Autodesk Fusion 360 part; units mm, degrees
(part 3 of 6)
sketch "A Seal Relief sketch" plane through (0.3536, 0.3536, 0) normal (0.707107, 0.707107, 0) x (0, 0, 1) in component "A Housing"
  circle A0 centre (0, 0) radius 9.75
  dimension "d695" = 19.5
  measures "d695" diameter of A0
extrude "A Seal Relief" cut sketch "A Seal Relief sketch" along normal blind 10.1 bodies 3 in component "A Housing"
ref_plane "WorkPlane21" through (0.3536, 0.3536, 12.125) normal (0.707107, 0.707107, 0) x (0, 0, 1) in component "A Housing"
sketch "A Front Bearing Seat sketch" plane through (0.3536, 0.3536, 0) normal (0.707107, 0.707107, 0) x (0, 0, 1) in component "A Housing"
  circle A0 centre (0, 0) radius 11.1
  dimension "d700" = 22.2
  measures "d700" diameter of A0
extrude "A Front Bearing Seat" cut sketch "A Front Bearing Seat sketch" along normal blind 7.1 bodies 3 in component "A Housing"
ref_plane "WorkPlane22" through (0.3536, 0.3536, 12.125) normal (0.707107, 0.707107, 0) x (0, 0, 1) in component "A Housing"
sketch "A Support Bolt seed" plane through (0.3536, 0.3536, 0) normal (0.707107, 0.707107, 0) x (0, 0, 1) in component "A Housing"
  line L0 (0, 0) -> (17, 0) construction
  circle A0 centre (17, 0) radius 1.65
  dimension "d705" = 17
  dimension "d706" = 3.3
  constraint horizontal L0
  measures "d705" distance of L0.start L0.end
  measures "d706" diameter of A0
extrude "A Support Bolt bore" cut sketch "A Support Bolt seed" along normal blind 10.1 bodies 3 in component "A Housing"
pattern_circular "A Support Bolt pattern" count 3 over 360 about axis through (0.3536, 0.3536, 0) along (0.707107, 0.707107, 0) of "A Support Bolt bore" in component "A Housing"
ref_plane "WorkPlane23" through (0.3536, 0.3536, 12.125) normal (0.707107, 0.707107, 0) x (0, 0, 1) in component "A Housing"
sketch "A Front Bearing Boss sketch" plane through (0.3536, 0.3536, 0) normal (0.707107, 0.707107, 0) x (0, 0, 1) in component "A Housing"
  circle A0 centre (0, 0) radius 22
  dimension "d713" = 44
  measures "d713" diameter of A0
chamfer "A Bearing Entry Chamfer" distance 0.4 angle 45 1 edges at (-2.4847, 3.1918, -10.3488) tangent chain off on bodies 3 in component "A Housing"
ref_plane "WorkPlane24" through (0, 0, 75) normal (0, 0, 1) x (1, 0, 0) in component "A Housing"
sketch "A Collar Driver Corridors" plane through (0, 0, 75) normal (0, 0, 1) x (1, 0, 0) in component "A Housing"
  circle A0 centre (6.7175, 15.9099) radius 3
  circle A1 centre (15.9099, 6.7175) radius 3
  dimension "d717" = 6.7175
  dimension "d718" = 15.9099
  dimension "d719" = 6
  dimension "d720" = 15.9099
  dimension "d721" = 6.7175
  dimension "d722" = 6
  measures "d717" horizontal distance of origin A0.centre
  measures "d718" vertical distance of origin A0.centre
  measures "d719" diameter of A0
  measures "d720" horizontal distance of origin A1.centre
  measures "d721" vertical distance of origin A1.centre
  measures "d722" diameter of A1
extrude "A Collar Service Channels" cut sketch "A Collar Driver Corridors" against normal blind 75 bodies 3 in component "A Housing"
ref_plane "WorkPlane17" through (-0.3536, -0.3536, 12.125) normal (0.707107, 0.707107, 0) x (0, 0, 1) in component "B Moving Body"
sketch "B Central Carrier sketch" plane through (-0.3536, -0.3536, 0) normal (0.707107, 0.707107, 0) x (0, 0, 1) in component "B Moving Body"
  circle A0 centre (0, 0) radius 38
  dimension "d727" = 76
  measures "d727" diameter of A0
extrude "B Central Carrier" add sketch "B Central Carrier sketch" against normal blind 22.5 separate body makes body 6 in component "B Moving Body"
ref_plane "WorkPlane18" through (-0.3536, -0.3536, 12.125) normal (0.707107, 0.707107, 0) x (0, 0, 1) in component "B Moving Body"
sketch "B Spoke 1 Profile" plane through (-0.3536, -0.3536, 0) normal (0.707107, 0.707107, 0) x (0, 0, 1) in component "B Moving Body"
  line L0 (-4.7984, -1.4054) -> (37.3643, -145.3579)
  line L1 (37.3643, -145.3579) -> (46.9611, -142.547)
  line L2 (46.9611, -142.547) -> (4.7984, 1.4054)
  line L3 (4.7984, 1.4054) -> (-4.7984, -1.4054)
  dimension "d732" = 4.7984
  dimension "d733" = 1.4054
  dimension "d734" = 37.3643
  dimension "d735" = 145.3579
  dimension "d736" = 46.9611
  dimension "d737" = 142.547
  dimension "d738" = 4.7984
  dimension "d739" = 1.4054
  measures "d732" horizontal distance of origin L0.start
  measures "d733" vertical distance of origin L0.start
  measures "d734" horizontal distance of origin L0.end
  measures "d735" vertical distance of origin L0.end
  measures "d736" horizontal distance of origin L1.end
  measures "d737" vertical distance of origin L1.end
  measures "d738" horizontal distance of origin L2.end
  measures "d739" vertical distance of origin L2.end
extrude "B Deep Spoke 1" add sketch "B Spoke 1 Profile" against normal blind 18 bodies 4 6 in component "B Moving Body"
sketch "B Spoke 2 Profile" plane through (-0.3536, -0.3536, 0) normal (0.707107, 0.707107, 0) x (0, 0, 1) in component "B Moving Body"
  line L0 (-2.5272, -4.3143) -> (126.9012, -80.1317)
  line L1 (126.9012, -80.1317) -> (131.9557, -71.5031)
  line L2 (131.9557, -71.5031) -> (2.5272, 4.3143)
  line L3 (2.5272, 4.3143) -> (-2.5272, -4.3143)
  dimension "d742" = 2.5272
  dimension "d743" = 4.3143
  dimension "d744" = 126.9012
  dimension "d745" = 80.1317
  dimension "d746" = 131.9557
  dimension "d747" = 71.5031
  dimension "d748" = 2.5272
  dimension "d749" = 4.3143
  measures "d742" horizontal distance of origin L0.start
  measures "d743" vertical distance of origin L0.start
  measures "d744" horizontal distance of origin L0.end
  measures "d745" vertical distance of origin L0.end
  measures "d746" horizontal distance of origin L1.end
  measures "d747" vertical distance of origin L1.end
  measures "d748" horizontal distance of origin L2.end
  measures "d749" vertical distance of origin L2.end
extrude "B Deep Spoke 2" add sketch "B Spoke 2 Profile" against normal blind 18 bodies 4 in component "B Moving Body"
sketch "B Spoke 3 Profile" plane through (-0.3536, -0.3536, 0) normal (0.707107, 0.707107, 0) x (0, 0, 1) in component "B Moving Body"
  line L0 (2.5272, -4.3143) -> (131.9557, 71.5031)
  line L1 (131.9557, 71.5031) -> (126.9012, 80.1317)
  line L2 (126.9012, 80.1317) -> (-2.5272, 4.3143)
  line L3 (-2.5272, 4.3143) -> (2.5272, -4.3143)
  dimension "d752" = 2.5272
  dimension "d753" = 4.3143
  dimension "d754" = 131.9557
  dimension "d755" = 71.5031
  dimension "d756" = 126.9012
  dimension "d757" = 80.1317
  dimension "d758" = 2.5272
  dimension "d759" = 4.3143
  measures "d752" horizontal distance of origin L0.start
  measures "d753" vertical distance of origin L0.start
  measures "d754" horizontal distance of origin L0.end
  measures "d755" vertical distance of origin L0.end
  measures "d756" horizontal distance of origin L1.end
  measures "d757" vertical distance of origin L1.end
  measures "d758" horizontal distance of origin L2.end
  measures "d759" vertical distance of origin L2.end
extrude "B Deep Spoke 3" add sketch "B Spoke 3 Profile" against normal blind 18 bodies 4 in component "B Moving Body"
sketch "B Spoke 4 Profile" plane through (-0.3536, -0.3536, 0) normal (0.707107, 0.707107, 0) x (0, 0, 1) in component "B Moving Body"
  line L0 (4.7984, -1.4054) -> (46.9611, 142.547)
  line L1 (46.9611, 142.547) -> (37.3643, 145.3579)
  line L2 (37.3643, 145.3579) -> (-4.7984, 1.4054)
  line L3 (-4.7984, 1.4054) -> (4.7984, -1.4054)
  dimension "d762" = 4.7984
  dimension "d763" = 1.4054
  dimension "d764" = 46.9611
  dimension "d765" = 142.547
  dimension "d766" = 37.3643
  dimension "d767" = 145.3579
  dimension "d768" = 4.7984
  dimension "d769" = 1.4054
  measures "d762" horizontal distance of origin L0.start
  measures "d763" vertical distance of origin L0.start
  measures "d764" horizontal distance of origin L0.end
  measures "d765" vertical distance of origin L0.end
  measures "d766" horizontal distance of origin L1.end
  measures "d767" vertical distance of origin L1.end
  measures "d768" horizontal distance of origin L2.end
  measures "d769" vertical distance of origin L2.end
extrude "B Deep Spoke 4" add sketch "B Spoke 4 Profile" against normal blind 18 bodies 4 in component "B Moving Body"
sketch "B Spoke 5 Profile" plane through (-0.3536, -0.3536, 0) normal (0.707107, 0.707107, 0) x (0, 0, 1) in component "B Moving Body"
  line L0 (4.7984, 1.4054) -> (-37.3643, 145.3579)
  line L1 (-37.3643, 145.3579) -> (-46.9611, 142.547)
  line L2 (-46.9611, 142.547) -> (-4.7984, -1.4054)
  line L3 (-4.7984, -1.4054) -> (4.7984, 1.4054)
  dimension "d772" = 4.7984
  dimension "d773" = 1.4054
  dimension "d774" = 37.3643
  dimension "d775" = 145.3579
  dimension "d776" = 46.9611
  dimension "d777" = 142.547
  dimension "d778" = 4.7984
  dimension "d779" = 1.4054
  measures "d772" horizontal distance of origin L0.start
  measures "d773" vertical distance of origin L0.start
  measures "d774" horizontal distance of origin L0.end
  measures "d775" vertical distance of origin L0.end
  measures "d776" horizontal distance of origin L1.end
  measures "d777" vertical distance of origin L1.end
  measures "d778" horizontal distance of origin L2.end
  measures "d779" vertical distance of origin L2.end
extrude "B Deep Spoke 5" add sketch "B Spoke 5 Profile" against normal blind 18 bodies 4 in component "B Moving Body"
sketch "B Spoke 6 Profile" plane through (-0.3536, -0.3536, 0) normal (0.707107, 0.707107, 0) x (0, 0, 1) in component "B Moving Body"
  line L0 (2.5272, 4.3143) -> (-126.9012, 80.1317)
  line L1 (-126.9012, 80.1317) -> (-131.9557, 71.5031)
  line L2 (-131.9557, 71.5031) -> (-2.5272, -4.3143)
  line L3 (-2.5272, -4.3143) -> (2.5272, 4.3143)
  dimension "d782" = 2.5272
  dimension "d783" = 4.3143
  dimension "d784" = 126.9012
  dimension "d785" = 80.1317
  dimension "d786" = 131.9557
  dimension "d787" = 71.5031
  dimension "d788" = 2.5272
  dimension "d789" = 4.3143
  measures "d782" horizontal distance of origin L0.start
  measures "d783" vertical distance of origin L0.start
  measures "d784" horizontal distance of origin L0.end
  measures "d785" vertical distance of origin L0.end
  measures "d786" horizontal distance of origin L1.end
  measures "d787" vertical distance of origin L1.end
  measures "d788" horizontal distance of origin L2.end
  measures "d789" vertical distance of origin L2.end
extrude "B Deep Spoke 6" add sketch "B Spoke 6 Profile" against normal blind 18 bodies 4 in component "B Moving Body"
sketch "B Spoke 7 Profile" plane through (-0.3536, -0.3536, 0) normal (0.707107, 0.707107, 0) x (0, 0, 1) in component "B Moving Body"
  line L0 (-2.5272, 4.3143) -> (-131.9557, -71.5031)
  line L1 (-131.9557, -71.5031) -> (-126.9012, -80.1317)
  line L2 (-126.9012, -80.1317) -> (2.5272, -4.3143)
  line L3 (2.5272, -4.3143) -> (-2.5272, 4.3143)
  dimension "d792" = 2.5272
  dimension "d793" = 4.3143
  dimension "d794" = 131.9557
  dimension "d795" = 71.5031
  dimension "d796" = 126.9012
  dimension "d797" = 80.1317
  dimension "d798" = 2.5272
  dimension "d799" = 4.3143
  measures "d792" horizontal distance of origin L0.start
  measures "d793" vertical distance of origin L0.start
  measures "d794" horizontal distance of origin L0.end
  measures "d795" vertical distance of origin L0.end
  measures "d796" horizontal distance of origin L1.end
  measures "d797" vertical distance of origin L1.end
  measures "d798" horizontal distance of origin L2.end
  measures "d799" vertical distance of origin L2.end
extrude "B Deep Spoke 7" add sketch "B Spoke 7 Profile" against normal blind 18 bodies 4 in component "B Moving Body"
sketch "B Spoke 8 Profile" plane through (-0.3536, -0.3536, 0) normal (0.707107, 0.707107, 0) x (0, 0, 1) in component "B Moving Body"
  line L0 (-4.7984, 1.4054) -> (-46.9611, -142.547)
  line L1 (-46.9611, -142.547) -> (-37.3643, -145.3579)
  line L2 (-37.3643, -145.3579) -> (4.7984, 1.4054)
  line L3 (4.7984, 1.4054) -> (-4.7984, 1.4054)
  dimension "d802" = 4.7984
  dimension "d803" = 1.4054
  dimension "d804" = 46.9611
  dimension "d805" = 142.547
  dimension "d806" = 37.3643
  dimension "d807" = 145.3579
  dimension "d808" = 4.7984
  dimension "d809" = 1.4054
  measures "d802" horizontal distance of origin L0.start
  measures "d803" vertical distance of origin L0.start
  measures "d804" horizontal distance of origin L0.end
  measures "d805" vertical distance of origin L0.end
  measures "d806" horizontal distance of origin L1.end
  measures "d807" vertical distance of origin L1.end
  measures "d808" horizontal distance of origin L2.end
  measures "d809" vertical distance of origin L2.end
extrude "B Deep Spoke 8" add sketch "B Spoke 8 Profile" against normal blind 18 bodies 4 in component "B Moving Body"
sketch "Spoke Outer Envelope (2)" plane through (0, 0, 0) normal (1, 0, 0) x (0, 0, -1) in component "B Moving Body"
  line L0 (75, 31.066) -> (31.066, 75)
  line L1 (31.066, 75) -> (-31.066, 75)
  line L2 (-31.066, 75) -> (-75, 31.066)
  line L3 (-75, 31.066) -> (-75, -31.066)
  line L4 (-75, -31.066) -> (-31.066, -75)
  line L5 (-31.066, -75) -> (31.066, -75)
  line L6 (31.066, -75) -> (75, -31.066)
  line L7 (75, -31.066) -> (75, 31.066)
  dimension "d812" = 150
  constraint horizontal L1
  measures "d812" vertical distance of L0.end L5.end
extrude "Clip Spokes to Octagon'" cut sketch "Spoke Outer Envelope (2)" along normal mid plane 260 keep common part bodies 4 in component "B Moving Body"
fillet "B Central Spoke Root Blends" radius 1 16 edges at (-31.2863, 17.8512, 15.3868) (3.6952, -17.1302, 35.0307) (-23.2315, 9.7965, 29.9762) (19.8388, -33.2738, -5.7899) (-23.2315, 9.7965, -29.9762) (-33.2076, 19.7726, -6.3678) (-31.2863, 17.8512, -15.3868) (-17.1302, 3.6952, -35.0307) (3.6952, -17.1302, -35.0307) (9.7965, -23.2315, -29.9762) (17.8512, -31.2863, -15.3868) (19.8388, -33.2738, 5.7899) (17.8512, -31.2863, 15.3868) (9.7965, -23.2315, 29.9762) (-17.1302, 3.6952, 35.0307) (-33.2738, 19.8388, 5.7899) on bodies 4 in component "B Moving Body"
ref_plane "WorkPlane19" through (-0.3536, -0.3536, 12.125) normal (0.707107, 0.707107, 0) x (0, 0, 1) in component "B Moving Body"
sketch "B Open Hub Cavity sketch" plane through (-0.3536, -0.3536, 0) normal (0.707107, 0.707107, 0) x (0, 0, 1) in component "B Moving Body"
  circle A0 centre (0, 0) radius 25.15
  dimension "d819" = 50.3
  measures "d819" diameter of A0
extrude "B Open Hub Cavity" cut sketch "B Open Hub Cavity sketch" against normal blind 22.5 bodies 4 in component "B Moving Body"
ref_plane "WorkPlane20" through (-0.3536, -0.3536, 12.125) normal (0.707107, 0.707107, 0) x (0, 0, 1) in component "B Moving Body"
sketch "B Four Mount Holes" plane through (-0.3536, -0.3536, 0) normal (0.707107, 0.707107, 0) x (0, 0, 1) in component "B Moving Body"
  circle A0 centre (22.6274, 22.6274) radius 2.15
  circle A1 centre (-22.6274, 22.6274) radius 2.15
  circle A2 centre (-22.6274, -22.6274) radius 2.15
  circle A3 centre (22.6274, -22.6274) radius 2.15
  dimension "d824" = 22.6274
  dimension "d825" = 22.6274
  dimension "d826" = 4.3
  dimension "d827" = 22.6274
  dimension "d828" = 22.6274
  dimension "d829" = 4.3
  dimension "d830" = 22.6274
  dimension "d831" = 22.6274
  dimension "d832" = 4.3
  dimension "d833" = 22.6274
  dimension "d834" = 22.6274
  dimension "d835" = 4.3
  measures "d824" horizontal distance of origin A0.centre
  measures "d825" vertical distance of origin A0.centre
  measures "d826" diameter of A0
  measures "d827" horizontal distance of origin A1.centre
  measures "d828" vertical distance of origin A1.centre
  measures "d829" diameter of A1
  measures "d830" horizontal distance of origin A2.centre
  measures "d831" vertical distance of origin A2.centre
  measures "d832" diameter of A2
  measures "d833" horizontal distance of origin A3.centre
  measures "d834" vertical distance of origin A3.centre
  measures "d835" diameter of A3
extrude "B M4 Through Holes" cut sketch "B Four Mount Holes" against normal blind 22.5 bodies 4 in component "B Moving Body"
sketch "B M4 Nut Pocket 1" plane through (-0.3536, -0.3536, 0) normal (0.707107, 0.707107, 0) x (0, 0, 1) in component "B Moving Body"
  circle A0 centre (22.6274, 22.6274) radius 4.1569 construction
  line L0 (26.7843, 22.6274) -> (24.7059, 26.2274)
  line L1 (24.7059, 26.2274) -> (20.549, 26.2274)
  line L2 (20.549, 26.2274) -> (18.4705, 22.6274)
  line L3 (18.4705, 22.6274) -> (20.549, 19.0274)
  line L4 (20.549, 19.0274) -> (24.7059, 19.0274)
  line L5 (24.7059, 19.0274) -> (26.7843, 22.6274)
  dimension "d838" = 22.6274
  dimension "d839" = 22.6274
  dimension "d840" = 8.3138
  constraint coincident A0 L0.start
  constraint coincident A0 L0.end
  constraint coincident A0 L1.end
  constraint coincident A0 L2.end
  constraint coincident A0 L3.end
  constraint coincident A0 L4.end
  constraint equal L0 L1
  constraint equal L0 L2
  constraint equal L0 L3
  constraint equal L0 L4
  constraint equal L0 L5
  constraint horizontal L1
  measures "d838" horizontal distance of origin A0.centre
  measures "d839" vertical distance of origin A0.centre
  measures "d840" diameter of A0
extrude "B Open M4 Nut Trap 1" cut sketch "B M4 Nut Pocket 1" against normal blind 4 bodies 4 in component "B Moving Body"
sketch "B M4 Nut Pocket 2" plane through (-0.3536, -0.3536, 0) normal (0.707107, 0.707107, 0) x (0, 0, 1) in component "B Moving Body"
  circle A0 centre (-22.6274, 22.6274) radius 4.1569 construction
  line L0 (-18.4705, 22.6274) -> (-20.549, 26.2274)
  line L1 (-20.549, 26.2274) -> (-24.7059, 26.2274)
  line L2 (-24.7059, 26.2274) -> (-26.7843, 22.6274)
  line L3 (-26.7843, 22.6274) -> (-24.7059, 19.0274)
  line L4 (-24.7059, 19.0274) -> (-20.549, 19.0274)
  line L5 (-20.549, 19.0274) -> (-18.4705, 22.6274)
  dimension "d843" = 22.6274
  dimension "d844" = 22.6274
  dimension "d845" = 8.3138
  constraint coincident A0 L0.start
  constraint coincident A0 L0.end
  constraint coincident A0 L1.end
  constraint coincident A0 L2.end
  constraint coincident A0 L3.end
  constraint coincident A0 L4.end
  constraint equal L0 L1
  constraint equal L0 L2
  constraint equal L0 L3
  constraint equal L0 L4
  constraint equal L0 L5
  constraint horizontal L1
  measures "d843" horizontal distance of origin A0.centre
  measures "d844" vertical distance of origin A0.centre
  measures "d845" diameter of A0
extrude "B Open M4 Nut Trap 2" cut sketch "B M4 Nut Pocket 2" against normal blind 4 bodies 4 in component "B Moving Body"
sketch "B M4 Nut Pocket 3" plane through (-0.3536, -0.3536, 0) normal (0.707107, 0.707107, 0) x (0, 0, 1) in component "B Moving Body"
  circle A0 centre (-22.6274, -22.6274) radius 4.1569 construction
  line L0 (-18.4705, -22.6274) -> (-20.549, -19.0274)
  line L1 (-20.549, -19.0274) -> (-24.7059, -19.0274)
  line L2 (-24.7059, -19.0274) -> (-26.7843, -22.6274)
  line L3 (-26.7843, -22.6274) -> (-24.7059, -26.2274)
  line L4 (-24.7059, -26.2274) -> (-20.549, -26.2274)
  line L5 (-20.549, -26.2274) -> (-18.4705, -22.6274)
  dimension "d848" = 22.6274
  dimension "d849" = 22.6274
  dimension "d850" = 8.3138
  constraint coincident A0 L0.start
  constraint coincident A0 L0.end
  constraint coincident A0 L1.end
  constraint coincident A0 L2.end
  constraint coincident A0 L3.end
  constraint coincident A0 L4.end
  constraint equal L0 L1
  constraint equal L0 L2
  constraint equal L0 L3
  constraint equal L0 L4
  constraint equal L0 L5
  constraint horizontal L1
  measures "d848" horizontal distance of origin A0.centre
  measures "d849" vertical distance of origin A0.centre
  measures "d850" diameter of A0
extrude "B Open M4 Nut Trap 3" cut sketch "B M4 Nut Pocket 3" against normal blind 4 bodies 4 in component "B Moving Body"
sketch "B M4 Nut Pocket 4" plane through (-0.3536, -0.3536, 0) normal (0.707107, 0.707107, 0) x (0, 0, 1) in component "B Moving Body"
  circle A0 centre (22.6274, -22.6274) radius 4.1569 construction
  line L0 (26.7843, -22.6274) -> (24.7059, -19.0274)
  line L1 (24.7059, -19.0274) -> (20.549, -19.0274)
  line L2 (20.549, -19.0274) -> (18.4705, -22.6274)
  line L3 (18.4705, -22.6274) -> (20.549, -26.2274)
  line L4 (20.549, -26.2274) -> (24.7059, -26.2274)
  line L5 (24.7059, -26.2274) -> (26.7843, -22.6274)
  dimension "d853" = 22.6274
  dimension "d854" = 22.6274
  dimension "d855" = 8.3138
  constraint coincident A0 L0.start
  constraint coincident A0 L0.end
  constraint coincident A0 L1.end
  constraint coincident A0 L2.end
  constraint coincident A0 L3.end
  constraint coincident A0 L4.end
  constraint equal L0 L1
  constraint equal L0 L2
  constraint equal L0 L3
  constraint equal L0 L4
  constraint equal L0 L5
  constraint horizontal L1
  measures "d853" horizontal distance of origin A0.centre
  measures "d854" vertical distance of origin A0.centre
  measures "d855" diameter of A0
extrude "B Open M4 Nut Trap 4" cut sketch "B M4 Nut Pocket 4" against normal blind 4 bodies 4 in component "B Moving Body"
sketch "B Hub Service Slots" plane through (0, 0, 0) normal (0, 0, 1) x (1, 0, 0) in component "B Moving Body"
  line L0 (-14.8492, 3.5355) -> (-30.4056, -12.0208)
  line L1 (-30.4056, -12.0208) -> (-12.0208, -30.4056)
  line L2 (-12.0208, -30.4056) -> (3.5355, -14.8492)
  line L3 (3.5355, -14.8492) -> (-14.8492, 3.5355)
  dimension "d858" = 14.8492
  dimension "d859" = 3.5355
  dimension "d860" = 30.4056
  dimension "d861" = 12.0208
  dimension "d862" = 12.0208
  dimension "d863" = 30.4056
  dimension "d864" = 3.5355
  dimension "d865" = 14.8492
  measures "d858" horizontal distance of origin L0.start
  measures "d859" vertical distance of origin L0.start
  measures "d860" horizontal distance of origin L0.end
  measures "d861" vertical distance of origin L0.end
  measures "d862" horizontal distance of origin L1.end
  measures "d863" vertical distance of origin L1.end
  measures "d864" horizontal distance of origin L2.end
  measures "d865" vertical distance of origin L2.end
extrude "B Hub Side Access" cut sketch "B Hub Service Slots" along normal mid plane 76 bodies 4 in component "B Moving Body"
component "A Housing" placed x (1, 0, 0) y (0, 1, 0) z (0, 0, 1) at (0, 0, 0)
component "B Moving Body" placed x (1, 0, 0) y (0, 1, 0) z (0, 0, 1) at (0, 0, 0)
equation "bodyWidth = 150 mm" comment "Regular octagon across flats; corner diameter is larger."
equation "bodyLength = 260 mm" comment "Overall straight length of the shared master blank."
equation "splitAngle = 45 deg" comment "Keep this lesson angle at45 degrees."
equation "faceGap = 1 mm" comment "Gap between the two printed joint faces."
equation "wall = 4.5 mm" comment "Integrated shell and side brace radial thickness."
equation "faceHalfWidth = bodyWidth * ( sqrt(2) - 1 ) / 2" comment "Half-width of each outer planar facet."
equation "memberWidth = 8 mm" comment "Nominal brace and corner chord width in a facet."
equation "nodeHalfWidth = faceHalfWidth - memberWidth / 2" comment "Chord centerlines measured from facet center."
equation "jointNodeQ = 7 mm" comment "First truss skeleton row from the center joint plane."
equation "endRim = 10 mm" comment "Uncut axial rim at each distant end."
equation "endNodeX = bodyLength / 2 - endRim + memberWidth / 2" comment "Last skeleton row before aperture inset."
equation "apertureRadius = 1.5 mm" comment "Rounded internal corners at triangular openings."
equation "spokeWidth = 10 mm" comment "Width of each deep bearing bulkhead spoke."
equation "spokeDepth = 18 mm" comment "Bulkhead depth normal to the diagonal joint face."
equation "carrierOD = 52 mm" comment "Outside of integrated A front bearing carrier."
equation "rearCarrierClearance = 46 mm" comment "Internal carrier relief above front bearing shoulder."
equation "tubeCornerChamfer = 0.5 mm" comment "Exposed outside octagon corner bevel."
equation "tubeRimChamfer = 0.3 mm" comment "End rim and print-contact edge relief."
equation "cordStation = bodyLength / 2 - endRim / 2" comment "Load-test cord port center measured along body X."
equation "bearingOD = 22 mm" comment "608 measured outside diameter."
equation "bearingID = 8 mm" comment "608 bore."
equation "bearingWidth = 7 mm" comment "608 width."
equation "seatAllowance = 0.2 mm" comment "Trial DIAMETRAL clearance; choose with printed coupon."
equation "seatDiameter = bearingOD + seatAllowance" comment "Measured fit controls this."
equation "coreOD = 44 mm" comment "Bearing holder outer diameter."
equation "raceRelief = 19.5 mm" comment "Outer-ring shoulder opening; verify seals."
equation "frontSeatDepth = 7.1 mm" comment "0.1 mm outer-ring axial allowance."
equation "rearSeatDepth = 7.2 mm" comment "0.2 mm outer-ring axial float."
equation "shoulder = 3 mm" comment "Backing behind each bearing seat."
equation "supportSpacer = 12 mm" comment "Purchased metal M3 spacer length."
equation "supportCircle = 34 mm" comment "Three M3 support bolts."
equation "supportSpacerOD = 6 mm" comment "Purchased spacer outside diameter."
equation "capThickness = 3 mm" comment "Both printed outer-ring retaining caps."
equation "m3Clearance = 3.3 mm" comment "M3 through holes."
equation "m4Clearance = 4.3 mm" comment "M4 through holes."
equation "qFront = faceGap / 2" comment "Front bearing starts at A mating face."
equation "qFrontBack = qFront + frontSeatDepth + shoulder" comment "End of integrated A holder."
equation "qRearBase = qFrontBack + supportSpacer" comment "Start of removable rear holder."
equation "qRearBearing = qRearBase + shoulder" comment "Rear bearing inner end."
equation "qRearEnd = qRearBearing + rearSeatDepth" comment "Rear holder outer end."
equation "bearingSpacing = qRearBearing - qFront" comment "Derived support-center spacing, not a bearing rating."
equation "mountOD = 76 mm" comment "B mount and F flange outside diameter."
equation "mountCircle = 64 mm" comment "Four M4 attachment holes."
equation "mountOpening = 50.3 mm" comment "B through opening."
equation "hubFace = -23 mm" comment "Metal hub flat mounting face."
equation "adapterThickness = 6 mm" comment "F flange and metal compression sleeve length."
equation "pilotDiameter = 50 mm" comment "F shallow centering pilot."
equation "pilotInside = 34 mm" comment "Clearance around metal hub."
equation "pilotHeight = 2 mm" comment "Short pilot only."
equation "hubHoleSpacing = 16 mm" comment "Metal Sonic hub square hole spacing."
equation "sleeveOD = 8 mm" comment "M4 metal compression sleeves."
equation "sleeveAllowance = 0.2 mm" comment "Trial DIAMETRAL sleeve clearance."
equation "shaftClearance = 8.5 mm" comment "F clearance hole; not a bearing."
equation "nutAF = 7.2 mm" comment "M4 nominal 7 AF nut trial pocket."
equation "nutDepth = 4 mm" comment "Open front M4 nut pocket."
equation "rootRadius = 1 mm" comment "Hub-to-wall blend."
equation "entryChamfer = 0.4 mm" comment "Assembly lead-in."
equation "bedRelief = 0.3 mm" comment "Bed-contact edge allowance."
equation "d59 = bodyWidth"
equation "d60 = bodyLength"
equation "d62 = splitAngle"
equation "d64 = -faceGap / 2"
equation "d65 = -faceGap / 2"
equation "d66 = wall"
equation "d67 = wall"
equation "d70 = bodyWidth / 2"
equation "d72 = abs(( 1 ) * ( ( ( 1 ) * jointNodeQ * sqrt(2) - bodyWidth / 2 * cos(0 deg) + ( ( -1 ) * nodeHalfWidth ) * sin(0 deg) ) + ( 0 ) * ( ( 1 ) * endNodeX - ( ( 1 ) * jointNodeQ * sqrt(2) - bodyWidth / 2 * cos(0 deg) + ( ( -1 ) * nodeHalfWidth ) * sin(0 deg) ) ) ) + ( 0 ) * ( ( -1 ) * nodeHalfWidth ))"
equation "d73 = abs(( 0 ) * ( ( ( 1 ) * jointNodeQ * sqrt(2) - bodyWidth / 2 * cos(0 deg) + ( ( -1 ) * nodeHalfWidth ) * sin(0 deg) ) + ( 0 ) * ( ( 1 ) * endNodeX - ( ( 1 ) * jointNodeQ * sqrt(2) - bodyWidth / 2 * cos(0 deg) + ( ( -1 ) * nodeHalfWidth ) * sin(0 deg) ) ) ) + ( -1 ) * ( ( -1 ) * nodeHalfWidth ))"
equation "d74 = abs(( 1 ) * ( ( ( 1 ) * jointNodeQ * sqrt(2) - bodyWidth / 2 * cos(0 deg) + ( ( 1 ) * nodeHalfWidth ) * sin(0 deg) ) + ( 0 ) * ( ( 1 ) * endNodeX - ( ( 1 ) * jointNodeQ * sqrt(2) - bodyWidth / 2 * cos(0 deg) + ( ( 1 ) * nodeHalfWidth ) * sin(0 deg) ) ) ) + ( 0 ) * ( ( 1 ) * nodeHalfWidth ))"
equation "d75 = abs(( 0 ) * ( ( ( 1 ) * jointNodeQ * sqrt(2) - bodyWidth / 2 * cos(0 deg) + ( ( 1 ) * nodeHalfWidth ) * sin(0 deg) ) + ( 0 ) * ( ( 1 ) * endNodeX - ( ( 1 ) * jointNodeQ * sqrt(2) - bodyWidth / 2 * cos(0 deg) + ( ( 1 ) * nodeHalfWidth ) * sin(0 deg) ) ) ) + ( -1 ) * ( ( 1 ) * nodeHalfWidth ))"
equation "d76 = abs(( 1 ) * ( ( ( 1 ) * jointNodeQ * sqrt(2) - bodyWidth / 2 * cos(0 deg) + ( ( -1 ) * nodeHalfWidth ) * sin(0 deg) ) + ( 0.666666666666667 ) * ( ( 1 ) * endNodeX - ( ( 1 ) * jointNodeQ * sqrt(2) - bodyWidth / 2 * cos(0 deg) + ( ( -1 ) * nodeHalfWidth ) * sin(0 deg) ) ) ) + ( 0 ) * ( ( -1 ) * nodeHalfWidth ))"
equation "d77 = abs(( 0 ) * ( ( ( 1 ) * jointNodeQ * sqrt(2) - bodyWidth / 2 * cos(0 deg) + ( ( -1 ) * nodeHalfWidth ) * sin(0 deg) ) + ( 0.666666666666667 ) * ( ( 1 ) * endNodeX - ( ( 1 ) * jointNodeQ * sqrt(2) - bodyWidth / 2 * cos(0 deg) + ( ( -1 ) * nodeHalfWidth ) * sin(0 deg) ) ) ) + ( -1 ) * ( ( -1 ) * nodeHalfWidth ))"
equation "d78 = -memberWidth / 2"
equation "d79 = -( wall + 0.2 mm )"
equation "d81 = abs(( 1 ) * ( ( ( 1 ) * jointNodeQ * sqrt(2) - bodyWidth / 2 * cos(0 deg) + ( ( 1 ) * nodeHalfWidth ) * sin(0 deg) ) + ( 0 ) * ( ( 1 ) * endNodeX - ( ( 1 ) * jointNodeQ * sqrt(2) - bodyWidth / 2 * cos(0 deg) + ( ( 1 ) * nodeHalfWidth ) * sin(0 deg) ) ) ) + ( 0 ) * ( ( 1 ) * nodeHalfWidth ))"
equation "d82 = abs(( 0 ) * ( ( ( 1 ) * jointNodeQ * sqrt(2) - bodyWidth / 2 * cos(0 deg) + ( ( 1 ) * nodeHalfWidth ) * sin(0 deg) ) + ( 0 ) * ( ( 1 ) * endNodeX - ( ( 1 ) * jointNodeQ * sqrt(2) - bodyWidth / 2 * cos(0 deg) + ( ( 1 ) * nodeHalfWidth ) * sin(0 deg) ) ) ) + ( -1 ) * ( ( 1 ) * nodeHalfWidth ))"
equation "d83 = abs(( 1 ) * ( ( ( 1 ) * jointNodeQ * sqrt(2) - bodyWidth / 2 * cos(0 deg) + ( ( -1 ) * nodeHalfWidth ) * sin(0 deg) ) + ( 0.666666666666667 ) * ( ( 1 ) * endNodeX - ( ( 1 ) * jointNodeQ * sqrt(2) - bodyWidth / 2 * cos(0 deg) + ( ( -1 ) * nodeHalfWidth ) * sin(0 deg) ) ) ) + ( 0 ) * ( ( -1 ) * nodeHalfWidth ))"
equation "d84 = abs(( 0 ) * ( ( ( 1 ) * jointNodeQ * sqrt(2) - bodyWidth / 2 * cos(0 deg) + ( ( -1 ) * nodeHalfWidth ) * sin(0 deg) ) + ( 0.666666666666667 ) * ( ( 1 ) * endNodeX - ( ( 1 ) * jointNodeQ * sqrt(2) - bodyWidth / 2 * cos(0 deg) + ( ( -1 ) * nodeHalfWidth ) * sin(0 deg) ) ) ) + ( -1 ) * ( ( -1 ) * nodeHalfWidth ))"
equation "d85 = abs(( 1 ) * ( ( ( 1 ) * jointNodeQ * sqrt(2) - bodyWidth / 2 * cos(0 deg) + ( ( 1 ) * nodeHalfWidth ) * sin(0 deg) ) + ( 0.833333333333333 ) * ( ( 1 ) * endNodeX - ( ( 1 ) * jointNodeQ * sqrt(2) - bodyWidth / 2 * cos(0 deg) + ( ( 1 ) * nodeHalfWidth ) * sin(0 deg) ) ) ) + ( 0 ) * ( ( 1 ) * nodeHalfWidth ))"
equation "d86 = abs(( 0 ) * ( ( ( 1 ) * jointNodeQ * sqrt(2) - bodyWidth / 2 * cos(0 deg) + ( ( 1 ) * nodeHalfWidth ) * sin(0 deg) ) + ( 0.833333333333333 ) * ( ( 1 ) * endNodeX - ( ( 1 ) * jointNodeQ * sqrt(2) - bodyWidth / 2 * cos(0 deg) + ( ( 1 ) * nodeHalfWidth ) * sin(0 deg) ) ) ) + ( -1 ) * ( ( 1 ) * nodeHalfWidth ))"
equation "d87 = memberWidth / 2"
equation "d88 = -( wall + 0.2 mm )"
equation "d90 = abs(( 1 ) * ( ( ( 1 ) * jointNodeQ * sqrt(2) - bodyWidth / 2 * cos(0 deg) + ( ( -1 ) * nodeHalfWidth ) * sin(0 deg) ) + ( 0.666666666666667 ) * ( ( 1 ) * endNodeX - ( ( 1 ) * jointNodeQ * sqrt(2) - bodyWidth / 2 * cos(0 deg) + ( ( -1 ) * nodeHalfWidth ) * sin(0 deg) ) ) ) + ( 0 ) * ( ( -1 ) * nodeHalfWidth ))"
equation "d91 = abs(( 0 ) * ( ( ( 1 ) * jointNodeQ * sqrt(2) - bodyWidth / 2 * cos(0 deg) + ( ( -1 ) * nodeHalfWidth ) * sin(0 deg) ) + ( 0.666666666666667 ) * ( ( 1 ) * endNodeX - ( ( 1 ) * jointNodeQ * sqrt(2) - bodyWidth / 2 * cos(0 deg) + ( ( -1 ) * nodeHalfWidth ) * sin(0 deg) ) ) ) + ( -1 ) * ( ( -1 ) * nodeHalfWidth ))"
equation "d92 = abs(( 1 ) * ( ( ( 1 ) * jointNodeQ * sqrt(2) - bodyWidth / 2 * cos(0 deg) + ( ( 1 ) * nodeHalfWidth ) * sin(0 deg) ) + ( 0.833333333333333 ) * ( ( 1 ) * endNodeX - ( ( 1 ) * jointNodeQ * sqrt(2) - bodyWidth / 2 * cos(0 deg) + ( ( 1 ) * nodeHalfWidth ) * sin(0 deg) ) ) ) + ( 0 ) * ( ( 1 ) * nodeHalfWidth ))"
equation "d93 = abs(( 0 ) * ( ( ( 1 ) * jointNodeQ * sqrt(2) - bodyWidth / 2 * cos(0 deg) + ( ( 1 ) * nodeHalfWidth ) * sin(0 deg) ) + ( 0.833333333333333 ) * ( ( 1 ) * endNodeX - ( ( 1 ) * jointNodeQ * sqrt(2) - bodyWidth / 2 * cos(0 deg) + ( ( 1 ) * nodeHalfWidth ) * sin(0 deg) ) ) ) + ( -1 ) * ( ( 1 ) * nodeHalfWidth ))"
equation "d94 = abs(( 1 ) * ( ( ( 1 ) * jointNodeQ * sqrt(2) - bodyWidth / 2 * cos(0 deg) + ( ( -1 ) * nodeHalfWidth ) * sin(0 deg) ) + ( 1 ) * ( ( 1 ) * endNodeX - ( ( 1 ) * jointNodeQ * sqrt(2) - bodyWidth / 2 * cos(0 deg) + ( ( -1 ) * nodeHalfWidth ) * sin(0 deg) ) ) ) + ( 0 ) * ( ( -1 ) * nodeHalfWidth ))"
equation "d95 = abs(( 0 ) * ( ( ( 1 ) * jointNodeQ * sqrt(2) - bodyWidth / 2 * cos(0 deg) + ( ( -1 ) * nodeHalfWidth ) * sin(0 deg) ) + ( 1 ) * ( ( 1 ) * endNodeX - ( ( 1 ) * jointNodeQ * sqrt(2) - bodyWidth / 2 * cos(0 deg) + ( ( -1 ) * nodeHalfWidth ) * sin(0 deg) ) ) ) + ( -1 ) * ( ( -1 ) * nodeHalfWidth ))"
equation "d96 = -memberWidth / 2"
equation "d97 = -( wall + 0.2 mm )"
equation "d99 = abs(( 1 ) * ( ( ( 1 ) * jointNodeQ * sqrt(2) - bodyWidth / 2 * cos(0 deg) + ( ( 1 ) * nodeHalfWidth ) * sin(0 deg) ) + ( 0.833333333333333 ) * ( ( 1 ) * endNodeX - ( ( 1 ) * jointNodeQ * sqrt(2) - bodyWidth / 2 * cos(0 deg) + ( ( 1 ) * nodeHalfWidth ) * sin(0 deg) ) ) ) + ( 0 ) * ( ( 1 ) * nodeHalfWidth ))"
equation "d100 = abs(( 0 ) * ( ( ( 1 ) * jointNodeQ * sqrt(2) - bodyWidth / 2 * cos(0 deg) + ( ( 1 ) * nodeHalfWidth ) * sin(0 deg) ) + ( 0.833333333333333 ) * ( ( 1 ) * endNodeX - ( ( 1 ) * jointNodeQ * sqrt(2) - bodyWidth / 2 * cos(0 deg) + ( ( 1 ) * nodeHalfWidth ) * sin(0 deg) ) ) ) + ( -1 ) * ( ( 1 ) * nodeHalfWidth ))"
equation "d101 = abs(( 1 ) * ( ( ( 1 ) * jointNodeQ * sqrt(2) - bodyWidth / 2 * cos(0 deg) + ( ( -1 ) * nodeHalfWidth ) * sin(0 deg) ) + ( 1 ) * ( ( 1 ) * endNodeX - ( ( 1 ) * jointNodeQ * sqrt(2) - bodyWidth / 2 * cos(0 deg) + ( ( -1 ) * nodeHalfWidth ) * sin(0 deg) ) ) ) + ( 0 ) * ( ( -1 ) * nodeHalfWidth ))"
equation "d102 = abs(( 0 ) * ( ( ( 1 ) * jointNodeQ * sqrt(2) - bodyWidth / 2 * cos(0 deg) + ( ( -1 ) * nodeHalfWidth ) * sin(0 deg) ) + ( 1 ) * ( ( 1 ) * endNodeX - ( ( 1 ) * jointNodeQ * sqrt(2) - bodyWidth / 2 * cos(0 deg) + ( ( -1 ) * nodeHalfWidth ) * sin(0 deg) ) ) ) + ( -1 ) * ( ( -1 ) * nodeHalfWidth ))"
equation "d103 = abs(( 1 ) * ( ( ( 1 ) * jointNodeQ * sqrt(2) - bodyWidth / 2 * cos(0 deg) + ( ( 1 ) * nodeHalfWidth ) * sin(0 deg) ) + ( 1 ) * ( ( 1 ) * endNodeX - ( ( 1 ) * jointNodeQ * sqrt(2) - bodyWidth / 2 * cos(0 deg) + ( ( 1 ) * nodeHalfWidth ) * sin(0 deg) ) ) ) + ( 0 ) * ( ( 1 ) * nodeHalfWidth ))"
equation "d104 = abs(( 0 ) * ( ( ( 1 ) * jointNodeQ * sqrt(2) - bodyWidth / 2 * cos(0 deg) + ( ( 1 ) * nodeHalfWidth ) * sin(0 deg) ) + ( 1 ) * ( ( 1 ) * endNodeX - ( ( 1 ) * jointNodeQ * sqrt(2) - bodyWidth / 2 * cos(0 deg) + ( ( 1 ) * nodeHalfWidth ) * sin(0 deg) ) ) ) + ( -1 ) * ( ( 1 ) * nodeHalfWidth ))"
equation "d105 = memberWidth / 2"
equation "d106 = -( wall + 0.2 mm )"
equation "d109 = apertureRadius"
equation "d112 = bodyWidth / 2"
equation "d114 = abs(( 1 ) * ( ( ( 1 ) * jointNodeQ * sqrt(2) - bodyWidth / 2 * cos(45 deg) + ( ( -1 ) * nodeHalfWidth ) * sin(45 deg) ) + ( 0 ) * ( ( 1 ) * endNodeX - ( ( 1 ) * jointNodeQ * sqrt(2) - bodyWidth / 2 * cos(45 deg) + ( ( -1 ) * nodeHalfWidth ) * sin(45 deg) ) ) ) + ( 0 ) * ( ( -1 ) * nodeHalfWidth ))"
equation "d115 = abs(( 0 ) * ( ( ( 1 ) * jointNodeQ * sqrt(2) - bodyWidth / 2 * cos(45 deg) + ( ( -1 ) * nodeHalfWidth ) * sin(45 deg) ) + ( 0 ) * ( ( 1 ) * endNodeX - ( ( 1 ) * jointNodeQ * sqrt(2) - bodyWidth / 2 * cos(45 deg) + ( ( -1 ) * nodeHalfWidth ) * sin(45 deg) ) ) ) + ( -1 ) * ( ( -1 ) * nodeHalfWidth ))"
equation "d116 = abs(( 1 ) * ( ( ( 1 ) * jointNodeQ * sqrt(2) - bodyWidth / 2 * cos(45 deg) + ( ( 1 ) * nodeHalfWidth ) * sin(45 deg) ) + ( 0 ) * ( ( 1 ) * endNodeX - ( ( 1 ) * jointNodeQ * sqrt(2) - bodyWidth / 2 * cos(45 deg) + ( ( 1 ) * nodeHalfWidth ) * sin(45 deg) ) ) ) + ( 0 ) * ( ( 1 ) * nodeHalfWidth ))"
equation "d117 = abs(( 0 ) * ( ( ( 1 ) * jointNodeQ * sqrt(2) - bodyWidth / 2 * cos(45 deg) + ( ( 1 ) * nodeHalfWidth ) * sin(45 deg) ) + ( 0 ) * ( ( 1 ) * endNodeX - ( ( 1 ) * jointNodeQ * sqrt(2) - bodyWidth / 2 * cos(45 deg) + ( ( 1 ) * nodeHalfWidth ) * sin(45 deg) ) ) ) + ( -1 ) * ( ( 1 ) * nodeHalfWidth ))"
equation "d118 = abs(( 1 ) * ( ( ( 1 ) * jointNodeQ * sqrt(2) - bodyWidth / 2 * cos(45 deg) + ( ( -1 ) * nodeHalfWidth ) * sin(45 deg) ) + ( 0.333333333333333 ) * ( ( 1 ) * endNodeX - ( ( 1 ) * jointNodeQ * sqrt(2) - bodyWidth / 2 * cos(45 deg) + ( ( -1 ) * nodeHalfWidth ) * sin(45 deg) ) ) ) + ( 0 ) * ( ( -1 ) * nodeHalfWidth ))"
equation "d119 = abs(( 0 ) * ( ( ( 1 ) * jointNodeQ * sqrt(2) - bodyWidth / 2 * cos(45 deg) + ( ( -1 ) * nodeHalfWidth ) * sin(45 deg) ) + ( 0.333333333333333 ) * ( ( 1 ) * endNodeX - ( ( 1 ) * jointNodeQ * sqrt(2) - bodyWidth / 2 * cos(45 deg) + ( ( -1 ) * nodeHalfWidth ) * sin(45 deg) ) ) ) + ( -1 ) * ( ( -1 ) * nodeHalfWidth ))"
equation "d120 = -memberWidth / 2"
equation "d121 = -( wall + 0.2 mm )"
equation "d123 = abs(( 1 ) * ( ( ( 1 ) * jointNodeQ * sqrt(2) - bodyWidth / 2 * cos(45 deg) + ( ( 1 ) * nodeHalfWidth ) * sin(45 deg) ) + ( 0 ) * ( ( 1 ) * endNodeX - ( ( 1 ) * jointNodeQ * sqrt(2) - bodyWidth / 2 * cos(45 deg) + ( ( 1 ) * nodeHalfWidth ) * sin(45 deg) ) ) ) + ( 0 ) * ( ( 1 ) * nodeHalfWidth ))"